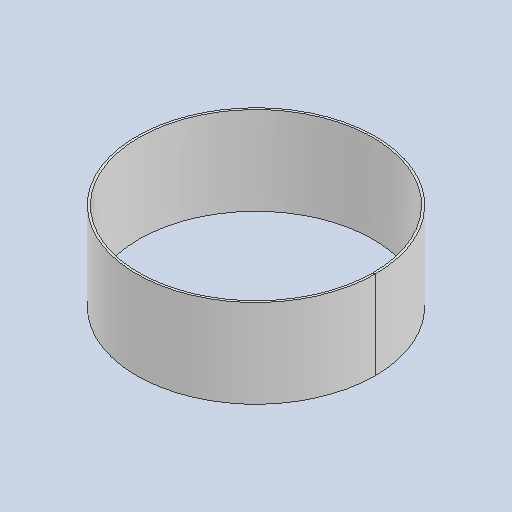
# Autodesk Inventor part: GBK-RK-0035 tube_CPY
Saved by Autodesk Inventor 2026 (Build 300175000, 175)
## iProperties
Created: 2026-09-14
Part Number: GBK-RK-0035 tube_CPY
Material: Generic
Document SubType Name: Sheet Metal
Designer: user
Mass: 364.072 g
Surface Area: 2495.03 cm^2
Volume: 364.072 cm^3
Density: 1 g/cm^3
Flat Pattern Width: 101.018 cm
Flat Pattern Length: 12 cm
Flat Pattern Area: 1212.22 cm^2
Sheet Metal Rule: По умолчанию_мм
Sheet Metal Width: 1010,181 мм
Sheet Metal Length: 120,000 мм
Sheet Metal Area: 121221,741 мм^2
Appearance: По умолчанию
Author: admin
Autodesk Inventor part; units mm, degrees
ref_plane "YZ Plane" through (0, 0, 0) normal (1, 0, 0) x (0, 1, 0)
ref_plane "XZ Plane" through (0, 0, 0) normal (0, 1, 0) x (-1, 0, 0)
ref_plane "XY Plane" through (0, 0, 0) normal (0, 0, 1) x (1, 0, 0)
sketch "Sketch1" plane through (0, 0, 0) normal (0, 0, 1) x (1, 0, 0)
  line L0 (0, 0) -> (0, 204.8418)
  line L1 (159.5, 0) -> (162.5, 0)
  line L2 (162.5, 0) -> (162.5, 120)
  line L3 (162.5, 120) -> (159.5, 120)
  line L4 (159.5, 120) -> (159.5, 0)
  line L5 (159.5, 0) -> (-162.5, 20) construction
  line L6 (-162.5, 20) -> (-162.5, 120) construction
  line L7 (-162.5, 120) -> (162.5, 120) construction
  point P0 (161, 0)
  point P1 (161, 120)
  dimension "d0" = 3
  dimension "d2" = 325
  dimension "d8" = 325
  dimension "d9" = 100
  dimension "d10" = 120
  constraints: 16 end point, 2 midpoint, 2 parallel, 2 perpendicular, 2 vertical, 1 horizontal, 1 point on line
  measures "d0" distance of L3.end L2.end
  measures "d2" diameter of L2 L0
  measures "d8" diameter of L6 L0
  measures "d9" distance of L5.end L6.end
  measures "d10" distance of point (161, 0) point (161, 120)
revolve "Revolution1" add sketch "Sketch1" angle 359.9 about axis through (0, 0, 0) along (0, 1, 0)
equation "\"d8\" = d2"
equation "\"BendRadius\" = Thickness"
equation "\"BendReliefWidth\" = Thickness"
equation "\"BendReliefDepth\" = 0.5 * Thickness"
equation "\"CornerReliefSize\" = 4 * Thickness"
equation "\"MinimumRemnant\" = 2 * Thickness"
equation "\"TransitionRadius\" = BendRadius"
equation "\"JacobiRadiusSize\" = BendRadius"
equation "\"GapSize\" = Thickness"
equation "\"Thickness\" = 3"
body "Solid1"
